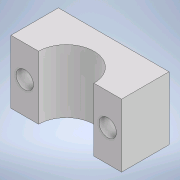
# Autodesk Inventor part: Motorhalterung_BT3
Saved by Autodesk Inventor 2020.1 (Build 241239000, 239)
## iProperties
Created: 2020-08-19
Part Number: Motorhalterung_BT3
Material: Generisch
Document SubType Name: Modeling
Designer: s5chfeis
Density: 1 g/cm^3
Appearance: Vorgabe
Author: s5chfeis
Autodesk Inventor part; units mm, degrees
ref_plane "YZ Plane" through (0, 0, 0) normal (1, 0, 0) x (0, 1, 0)
ref_plane "XZ Plane" through (0, 0, 0) normal (0, 1, 0) x (-1, 0, 0)
ref_plane "XY Plane" through (0, 0, 0) normal (0, 0, 1) x (1, 0, 0)
sketch "Skizze1" plane through (0, 0, 0) normal (0, 1, 0) x (-1, 0, 0)
  line L0 (0, 0) -> (70, 0)
  line L1 (70, 0) -> (70, -30)
  line L2 (70, -30) -> (0, -30)
  line L3 (0, -30) -> (0, 0)
  dimension "d0" = 70
  dimension "d1" = 30
  constraints: 8 end point, 2 parallel, 1 horizontal, 1 perpendicular
  measures "d0" distance of L1.end L2.end
  measures "d1" distance of L0.end L1.end
extrude "Extrusion1" add sketch "Skizze1" along normal blind 40
sketch "Skizze2" plane through (0, 40, 0) normal (0, 1, 0) x (1, 0, 0)
  line L0 (-70, 0) -> (0, 0) projected
  circle A0 centre (-35, 0) radius 17.5
  point P0 (-17.5, 0)
  point P1 (-52.5, 0)
  dimension "d4" = 35
  constraints: 1 centre point, 1 midpoint
  measures "d4" diameter of A0
extrude "Extrusion2" cut sketch "Skizze2" against normal blind 40 contours A0 L0 picked at (-30.8032, 5.2642)
sketch "Skizze4" plane through (0, 0, 0) normal (0, 0, 1) x (1, 0, 0)
  line L0 (-17.5, 40) -> (-17.5, 0) construction
  line L1 (0, 0) -> (-17.5, 40) construction
  line L2 (0, 0) -> (0, 40) construction
  line L3 (0, 40) -> (-17.5, 0) construction
  line L4 (0, 0) -> (-70, 0) construction
  line L5 (-35, 0) -> (-35, 40) construction
  line L6 (0, 40) -> (-70, 40) construction
  line L7 (-52.5, 40) -> (-52.5, 0) construction
  line L8 (-70, 0) -> (-52.5, 40) construction
  line L9 (-70, 0) -> (-70, 40) construction
  line L10 (-70, 40) -> (-52.5, 0) construction
  point P0 (-8.75, 20)
  point P1 (-61.25, 20)
  constraints: 14 end point, 3 midpoint, 3 symmetric about line
hole "Bohrung1" at (-8.75, 20, 0) at (-61.25, 20, 0) direction (0, 0, -1) diameter 11 depth 30 tip angle 118
